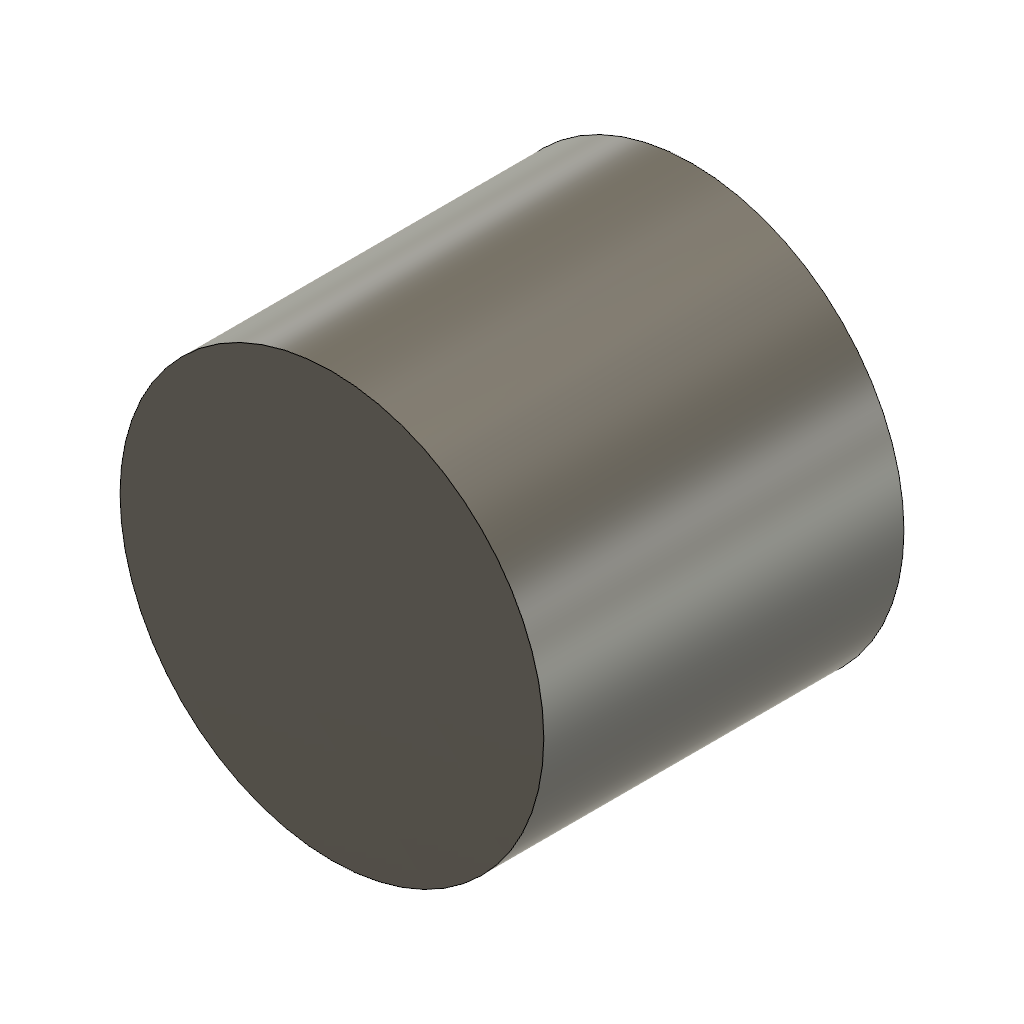
concentric_disk (Autodesk Fusion 360 design; units mm, degrees)
part number: 2026-10-20-18-34-04-259
Autodesk Fusion 360 part; units mm, degrees
sketch "MultipleProfiles" plane through (0, 0, 0) normal (0, 0, 1) x (1, 0, 0)
  circle A0 centre (0, 0) radius 10
  circle A1 centre (0, 0) radius 20
extrude "SelectedRegionExtrusion" add sketch "MultipleProfiles" along normal blind 17 contours A0
